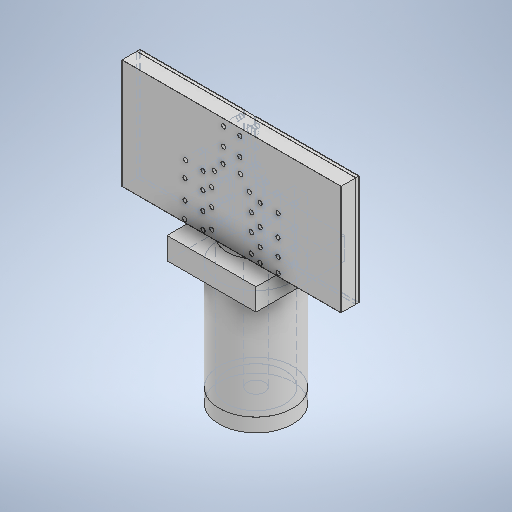
# Autodesk Inventor part: 08_coonector_plus_02mm_4layers
Saved by Autodesk Inventor 2025.3 (Build 293356000, 356)
## iProperties
Created: 2026-10-17
Part Number: 08_coonector_plus_02mm_4layers
Material: Generisch
Document SubType Name: Modeling
Designer: v.ivko
Density: 1 g/cm^3
Appearance: Vorgabe
Author: v.ivko
Autodesk Inventor part; units mm, degrees
ref_plane "YZ Plane" through (0, 0, 0) normal (1, 0, 0) x (0, 1, 0)
ref_plane "XZ Plane" through (0, 0, 0) normal (0, 1, 0) x (-1, 0, 0)
ref_plane "XY Plane" through (0, 0, 0) normal (0, 0, 1) x (1, 0, 0)
sketch "Skizze1" plane through (0, 0, 0) normal (0, 0, 1) x (1, 0, 0)
  line L0 (-8, -4) -> (8, -4)
  line L1 (8, -4) -> (8, 4)
  line L2 (8, 4) -> (-8, 4)
  line L3 (-8, 4) -> (-8, -4)
  line L4 (-8, -4) -> (8, 4) construction
  line L5 (8, -4) -> (-8, 4) construction
  point P0 (0, 0)
  dimension "d39" = 16
  dimension "d42" = 8
  constraints: 12 end point, 2 midpoint, 2 parallel, 1 horizontal, 1 perpendicular
  measures "d39" distance between parallel lines of L1 L3
  measures "d42" distance of L0.end L1.end
extrude "Extrusion1" add sketch "Skizze1" along normal blind 0.2
sketch "Skizze2" plane through (-8, -4, 0) normal (0, -1, 0) x (1, 0, 0)
  line L0 (8, 0) -> (8, -43.5363) construction
  line L1 (11.25, 2.75) -> (4.75, 2.75)
  line L2 (4.75, 2.75) -> (4.75, -3.75)
  line L3 (4.75, -3.75) -> (11.25, -3.75)
  line L4 (11.25, -3.75) -> (11.25, 2.75)
  line L5 (11.25, 2.75) -> (4.75, -3.75) construction
  line L6 (4.75, 2.75) -> (11.25, -3.75) construction
  line L7 (0, 0) -> (16, 0) projected
  circle A0 centre (8, -0.5) radius 2.11
  circle A1 centre (8, -0.5) radius 0.5 construction
  point P0 (11.25, 0)
  point P1 (4.75, 0)
  point P2 (5.9501, 0)
  point P3 (10.0499, 0)
  dimension "d2" = 6.5
  dimension "d3" = 6.5
  dimension "d4" = 0.5
  dimension "d27" = 4.22
  dimension "d30" = 1
  constraints: 14 end point, 2 centre point, 2 coincident, 2 midpoint, 2 parallel, 1 horizontal, 1 perpendicular, 1 point on line, 1 vertical
  measures "d2" distance of L2.end L3.end
  measures "d3" distance of L1.end L2.end
  measures "d4" distance from line of L7 point (8, -0.5)
  measures "d27" diameter of A0
  measures "d30" diameter of A1
extrude "Extrusion2" add sketch "Skizze2" along normal blind 1.6 separate body contours L4 L7 A0 L2 L1 | L4 L3 L2 L7 A0
sketch "Skizze3" plane through (-8, -5.6, 0) normal (0, -1, 0) x (1, 0, 0)
  circle A0 centre (8, -0.5) radius 2.11 projected
  circle A1 centre (8, -0.5) radius 2.675
  point P0 (8, 0)
  dimension "d28" = 5.35
  constraints: 1 centre point, 1 coincident
  measures "d28" diameter of A1
extrude "Extrusion3" add sketch "Skizze3" along normal blind 8 bodies 2
sketch "Skizze4" plane through (0, -13.6, -0.5) normal (0, -1, 0) x (1, 0, 0)
  circle A0 centre (0, 0) radius 0.635
  circle A1 centre (0, 0) radius 2.11 projected
  point P0 (0, 0.5)
  dimension "d29" = 1.27
  constraints: 1 centre point
  measures "d29" diameter of A0
extrude "Extrusion4" add sketch "Skizze4" against normal up to surface (9.6 mm away) separate body
sketch "Skizze5" plane through (0, -13.6, -0.5) normal (0, -1, 0) x (1, 0, 0)
  circle A0 centre (0, 0) radius 0.635
  point P0 (0, 0.5)
  dimension "d31" = 1.27
  constraints: 1 centre point
  measures "d31" diameter of A0
extrude "Extrusion5" add sketch "Skizze5" against normal up to surface (9.6 mm away) separate body
sketch "Skizze6" plane through (0, -4, -0.5) normal (0, 1, 0) x (1, 0, 0)
  circle A0 centre (0, 0) radius 0.635 projected
  circle A1 centre (0, 0) radius 0.5
  point P0 (0, -0.5)
  dimension "d98" = 1
  constraints: 1 centre point, 1 coincident
  measures "d98" diameter of A1
extrude "Extrusion6" add sketch "Skizze6" along normal blind 4 contours A1 bodies 4
sketch "Skizze7" plane through (-8, -4, 0) normal (0, 1, 0) x (1, 0, 0)
  line L0 (4.75, 0.035) -> (5.75, 0.035)
  line L1 (5.75, 0.035) -> (5.75, 1.035)
  line L2 (5.75, 1.035) -> (4.75, 1.035)
  line L3 (4.75, 1.035) -> (4.75, 0.035)
  line L4 (4.75, 0.035) -> (5.75, 1.035) construction
  line L5 (5.75, 0.035) -> (4.75, 1.035) construction
  circle A0 centre (8, 0.5) radius 0.635 projected
  line L6 (8, 0.5) -> (8, 3.9078) construction
  line L7 (16, 0) -> (0, 0) projected
  line L8 (4.75, -2.75) -> (4.75, 3.75) projected
  line L9 (11.25, 0.035) -> (10.25, 0.035)
  line L10 (10.25, 0.035) -> (10.25, 1.035)
  line L11 (10.25, 1.035) -> (11.25, 1.035)
  line L12 (11.25, 1.035) -> (11.25, 0.035)
  point P0 (8, 0)
  point P1 (5.25, 0.535)
  dimension "d15" = 1
  dimension "d16" = 1
  dimension "d17" = 0.035
  constraints: 22 end point, 4 symmetric about line, 2 midpoint, 2 parallel, 1 collinear, 1 horizontal, 1 perpendicular, 1 vertical
  measures "d15" distance of L1.end L2.end
  measures "d16" distance of L2.end L0.start
  measures "d17" distance between parallel lines of L7 L0
extrude "Extrusion7" add sketch "Skizze7" along normal blind 4 contours L3 L2 L1 L0 | L9 L10 L11 L12 bodies 2
sketch "Skizze8" plane through (0, 0, 0) normal (0, 0, -1) x (-1, 0, 0)
  line L0 (-0.5, -4) -> (0.5, -4)
  line L1 (8, -4) -> (-8, -4) projected
  line L2 (8, 4) -> (8, -4) projected
  line L3 (-8, -4) -> (-8, 4) projected
  line L4 (0, 0) -> (0, -24.5211) construction
  line L5 (0, 2.3181) -> (0, -4) construction
  line L6 (-1.1811, -4) -> (-8, -4)
  line L7 (-8, -4) -> (-8, 4)
  line L8 (-8, 4) -> (-1.1811, 4)
  line L9 (1.1811, -4) -> (8, -4)
  line L10 (8, -4) -> (8, 4)
  line L11 (8, 4) -> (1.1811, 4)
  line L12 (0.5, 0) -> (-0.5, 0) projected
  line L13 (0, 2.0749) -> (-0.0043, 2.0749)
  line L14 (1.1811, 4) -> (-1.1811, 4)
  line L15 (1.1, -4.6) -> (-1.1, -4.6)
  line L16 (-0.75, -4.25) -> (0.75, -4.25)
  line L17 (-0.15, 1) -> (-0.15, 3.2051)
  line L18 (0.15, 3.2051) -> (0.15, 1)
  line L19 (0.15, 1) -> (-0.15, 3.2051) construction
  line L20 (-0.15, 1) -> (0.15, 3.2051) construction
  line L21 (0.5, 0) -> (0.15, 1)
  line L22 (-0.15, 1) -> (-0.5, 0)
  line L23 (-0.5, 0) -> (-0.5, -4)
  line L24 (-0.5, -4) -> (-0.5, 0) projected
  line L25 (0.5, -4) -> (0.5, 0)
  line L26 (1.1, 0) -> (1.1, -4.6)
  line L27 (1.1, -4.6) -> (-1.1, -4.6)
  line L28 (-1.1, -4.6) -> (-1.1, 0)
  line L29 (-0.4, 1.0425) -> (-0.4, 3.4551)
  line L30 (0.4, 3.4551) -> (0.4, 1.0425)
  line L31 (0.75, -4) -> (0.75, -4.25)
  line L32 (0.75, -4.25) -> (-0.75, -4.25)
  line L33 (-0.75, -4.25) -> (-0.75, -4)
  line L34 (-1.1, 0) -> (-0.4, 1.0425)
  line L35 (1.1, 0) -> (0.4, 1.0425)
  line L36 (0.4, 3.4551) -> (0.4, 4)
  line L37 (-0.4, 3.4551) -> (-0.4, 4)
  line L38 (-0.15, 3.2051) -> (0.15, 3.2051)
  point P0 (-0.6947, -4)
  point P1 (0.6947, -4)
  point P2 (-0.5, -4)
  point P3 (0, 2.1025)
  point P4 (1.1, -4)
  point P5 (-1.1, -4)
  dimension "d118" = 0.3
  dimension "d119" = 1
  dimension "d120" = 1
  constraints: 68 end point, 8 equal length, 8 point on line, 4 perpendicular, 3 collinear, 3 horizontal, 3 midpoint, 1 symmetric about line, 1 vertical
  measures "d118" distance between parallel lines of L18 L17
  measures "d119" distance from line of L12 L17.start
  measures "d120" distance from line of L12 L18.end
extrude "Extrusion8" add sketch "Skizze8" along normal blind 0.035 separate body contours L23 L12 L25 L0 | L22 L17 L38 L18 L21 L12 | L1 L3 L8 L14 L37 L29 L34 L28 | L26 L35 L30 L36 L14 L11 L2 L1
sketch "Skizze9" plane through (0, 0, 0.2) normal (0, 0, 1) x (1, 0, 0)
  line L0 (8, -4) -> (8, 4) projected
  line L1 (8, 4) -> (-8, 4) projected
  line L2 (-8, 4) -> (-8, -4) projected
  line L3 (-8, -4) -> (8, -4) projected
  point P0 (0, 0)
extrude "Extrusion9" add sketch "Skizze9" along normal blind 0.0152 separate body
sketch "Skizze10" plane through (0, 0, -0.5) normal (0, 1, 0) x (1, 0, 0)
  circle A0 centre (0, 0) radius 0.635 projected
  line L0 (0.635, 0) -> (0.635, 0.1708) construction
  line L1 (-0.5, -0.5) -> (-0.5, -0.465) construction
  line L2 (0.5, -0.5) -> (0.5, -0.465) construction
  line L3 (-0.5, -0.5) -> (0.5, -0.5)
  line L4 (0.5, -0.5) -> (0.5, 0)
  line L5 (0.5, 0) -> (-0.5, 0)
  line L6 (-0.5, 0) -> (-0.5, -0.5)
  point P0 (-0.635, 0)
  constraints: 10 end point, 2 collinear, 2 parallel, 2 point on circle, 1 horizontal, 1 perpendicular, 1 tangent, 1 vertical
extrude "Extrusion10" add sketch "Skizze10" against normal blind 3.5 separate body contours L6 L5 L4 A0 L3 | A0 L3 L6 | L4 L3 A0
sketch "Skizze11" plane through (0, -13.6, -0.5) normal (0, -1, 0) x (1, 0, 0)
  line L0 (-0.635, 0) -> (0.635, 0) projected
  circle A0 centre (0, 0) radius 2.675
  point P0 (0, 0.5)
  constraints: 1 centre point, 1 midpoint
extrude "Extrusion11" add sketch "Skizze11" along normal blind 1 separate body
sketch "Skizze17" plane through (0.15, -4.7177, 0) normal (1, 0, 0) x (0, 0, -1)
  circle A0 centre (0.0175, 7.5546) radius 0.25
  line L0 (0.035, 7) -> (0, 7) projected
  line L1 (0.0175, 7) -> (0.0175, 6.5049) construction
  point P0 (0, 4.7177)
  dimension "d77" = 0.5
  constraints: 2 end point, 1 centre point, 1 midpoint, 1 point on line, 1 vertical
  measures "d77" diameter of A0
extrude "Extrusion17" add sketch "Skizze17" along normal up to surface (0.25 mm away) separate body
sketch "Skizze18" plane through (0, 0, 0.2152) normal (0, 0, 1) x (1, 0, 0)
  line L0 (0, 3.4504) -> (0, -9.381) construction
  line L1 (-1.25, -5.5772) -> (1.25, -5.5772)
  line L2 (1.25, -5.5772) -> (1.25, 0.0016)
  line L3 (1.25, 0.0016) -> (-1.25, 0.0016)
  line L4 (-1.25, 0.0016) -> (-1.25, -5.5772)
  line L5 (-1.25, -5.5772) -> (1.25, 0.0016) construction
  line L6 (1.25, -5.5772) -> (-1.25, 0.0016) construction
  line L7 (-0.4, 0.4784) -> (0.4, 1.0398) construction
  line L8 (0.4, 0.4784) -> (-0.4, 1.0398) construction
  line L9 (0.8561, 0.0016) -> (0.15, 1)
  line L10 (-0.15, 1) -> (-0.15, 3.2051) projected
  line L11 (0.15, 1) -> (-0.15, 1)
  line L12 (-0.8561, 0.0016) -> (-0.15, 1)
  line L13 (-0.15, 1) -> (0.15, 1)
  point P0 (0, 0)
  point P1 (0, -2.7878)
  point P2 (0, 0.7591)
  dimension "d99" = 2.5
  dimension "d100" = 0.8
  constraints: 26 end point, 4 midpoint, 3 equal length, 3 point on line, 2 perpendicular, 1 horizontal, 1 symmetric about line, 1 vertical
  measures "d99" distance of L2.end L3.end
  measures "d100" distance of L7.end L8.end
extrude "Extrusion18" cut sketch "Skizze18" against normal up to surface (0.0152 mm away) bodies 6
sketch "Skizze19" plane through (0, 0, 0.2152) normal (0, 0, 1) x (1, 0, 0)
  line L0 (8, 4) -> (-8, 4) projected
  line L1 (-8, 4) -> (-8, -4) projected
  line L2 (8, -4) -> (8, 4) projected
  line L3 (-8, -4) -> (8, -4) projected
  line L4 (-8, -4) -> (8, -4)
  point P0 (0, 0)
  constraints: 2 end point, 1 perpendicular
extrude "substrate2" add sketch "Skizze19" along normal blind 1.065 separate body
sketch "Skizze20" plane through (0, 0, 1.2802) normal (0, 0, 1) x (1, 0, 0)
  line L0 (-8, -4) -> (8, -4) projected
  line L1 (8, -4) -> (8, 4) projected
  line L2 (8, 4) -> (-8, 4) projected
  line L3 (-8, 4) -> (-8, -4) projected
  point P0 (0, 0)
extrude "L3_pec" add sketch "Skizze20" along normal blind 0.0152 separate body
sketch "Skizze13" plane through (0, 0, -0.035) normal (0, 0, -1) x (-1, 0, 0)
  circle A0 centre (-3.4019, -0.0075) radius 0.15
  circle A1 centre (-3.4019, -1.5368) radius 0.15
  circle A2 centre (-2.0875, -1.5368) radius 0.15
  circle A3 centre (-2.0875, -2.8052) radius 0.15
  circle A4 centre (3.3532, -0.0075) radius 0.15
  circle A5 centre (2.0862, -1.287) radius 0.15
  circle A6 centre (3.3969, -1.1872) radius 0.15
  circle A7 centre (2.0862, -2.5977) radius 0.15
  circle A8 centre (-1.2987, 0.2989) radius 0.15
  circle A9 centre (1.2484, 0.3547) radius 0.15
  circle A10 centre (-0.6612, 1.1129) radius 0.15
  circle A11 centre (-0.6044, 2.175) radius 0.15
  circle A12 centre (0.6225, 1.1129) radius 0.15
  circle A13 centre (0.576, 2.2215) radius 0.15
  circle A14 centre (-0.6044, 3.503) radius 0.15
  circle A15 centre (0.576, 3.503) radius 0.15
  circle A16 centre (-2.0875, -0.0075) radius 0.15
  circle A17 centre (2.0862, -0.0575) radius 0.15
  circle A18 centre (-1.4487, -0.9226) radius 0.15
  circle A19 centre (-1.4487, -2.1759) radius 0.15
  circle A20 centre (-1.4487, -3.5276) radius 0.15
  circle A21 centre (1.4421, -0.7726) radius 0.15
  circle A22 centre (1.4421, -2.0259) radius 0.15
  circle A23 centre (1.4421, -3.454) radius 0.15
  circle A24 centre (3.3969, -2.5977) radius 0.15
  circle A25 centre (3.4157, -3.7898) radius 0.15
  circle A26 centre (2.08, -3.7898) radius 0.15
  circle A27 centre (-3.4019, -2.7477) radius 0.15
  circle A28 centre (-2.0875, -3.7898) radius 0.15
  circle A29 centre (-3.4019, -3.7898) radius 0.15
  dimension "d45" = 0.3
  dimension "d46" = 0.3
  dimension "d47" = 0.3
  dimension "d48" = 0.3
  dimension "d49" = 0.3
  dimension "d50" = 0.3
  dimension "d51" = 0.3
  dimension "d52" = 0.3
  dimension "d53" = 0.3
  dimension "d61" = 0.3
  dimension "d83" = 0.3
  dimension "d84" = 0.3
  dimension "d85" = 0.3
  dimension "d86" = 0.3
  dimension "d87" = 0.3
  dimension "d88" = 0.3
  dimension "d89" = 0.3
  dimension "d90" = 0.3
  dimension "d91" = 0.3
  dimension "d92" = 0.3
  dimension "d93" = 0.3
  dimension "d94" = 0.3
  dimension "d95" = 0.3
  dimension "d96" = 0.3
  dimension "d111" = 0.3
  dimension "d112" = 0.3
  dimension "d113" = 0.3
  dimension "d114" = 0.3
  dimension "d115" = 0.3
  dimension "d116" = 0.3
  constraints: 30 centre point
  measures "d45" diameter of A0
  measures "d46" diameter of A1
  measures "d47" diameter of A2
  measures "d48" diameter of A3
  measures "d49" diameter of A4
  measures "d50" diameter of A5
  measures "d51" diameter of A6
  measures "d52" diameter of A7
  measures "d53" diameter of A8
  measures "d61" diameter of A9
  measures "d83" diameter of A10
  measures "d84" diameter of A11
  measures "d85" diameter of A12
  measures "d86" diameter of A13
  measures "d87" diameter of A14
  measures "d88" diameter of A15
  measures "d89" diameter of A16
  measures "d90" diameter of A17
  measures "d91" diameter of A18
  measures "d92" diameter of A19
  measures "d93" diameter of A20
  measures "d94" diameter of A21
  measures "d95" diameter of A22
  measures "d96" diameter of A23
  measures "d111" diameter of A24
  measures "d112" diameter of A25
  measures "d113" diameter of A26
  measures "d114" diameter of A27
  measures "d115" diameter of A28
  measures "d116" diameter of A29
extrude "vias" cut sketch "Skizze13" against normal blind 10 bodies 5 1 6 10 11
